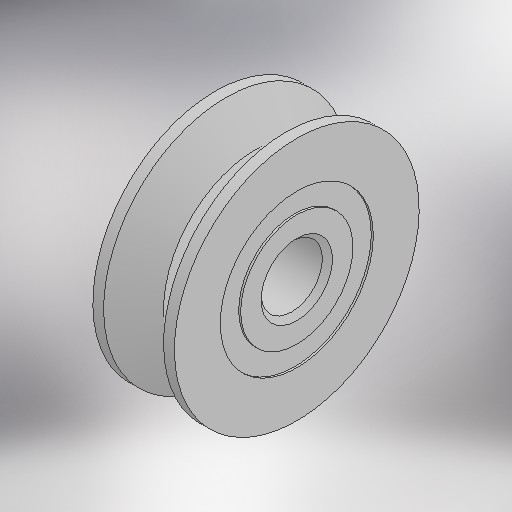
# Autodesk Inventor part: SZV4-12
Saved by Autodesk Inventor 2025.3 (Build 293356030, 356C)
## iProperties
Category: PARTsolutions
Company: MISUMI
Created: 2025-10-17
Part Number: SZV4-12
Material: Generic
Catalog Web Link: www.cadenas.de
Description: SZV, SZU, SZG-Stainless Steel Deep Groove Bearings
Vendor: MISUMI
Document SubType Name: Modeling
Designer: psAdmin
Manufacturer: MISUMI
Mass: 0.322411 g
Surface Area: 4.33482 cm^2
Volume: 0.322411 cm^3
Density: 1 g/cm^3
Appearance: PSOLRGB-175-175-175
PSOL_IDENT_0: {$CADENAS_DATA/23d-libs/misumi/metric/12_bearing_holders/szg.prj},166 {VTYP=3D},{NB=SZV4-12},{LINA=S
PSOL_IDENT_1: ZV4-12},{NN=SZV, SZU, SZG},{DATE=30.06.2021 12:59:26},{GEOMDATE=01.04.2010 04:21:00},{VERSION=},{LIN
PSOL_IDENT_2: EID=30},{WBVAR=TS,D},{WBNUMERIC=D}  {NB=SZV4-12},{LINA=SZV4-12},{KT=DUMMY},{PN=SZV4-12},{TS=V},{MATB=
PSOL_IDENT_3: 440C Stainless Steel},{DD=4},{D=12},{DALG=12,14},{B=4},{VD=9.06},{UD=0.00},{GD=0.00},{UR=0.00},{GR=0
PSOL_IDENT_4: },{C=0.25},{R=0.00},{CRR=542},{COO=186},{DSS=5.5},{DDHH=7.5},{WEIGHT=1.2},{TYPE=SZV}
NB: SZV4-12
NN: SZV, SZU, SZG
NT: Stainless Steel Deep Groove Bearings
NBSYN: $PN.
LINA: SZV4-12
CATALOG: Misumi
PN: SZV4-12
TS: SZV
MATB: 440C Stainless Steel
DD: 4
D: 12
B: 4
VD: 9.06
UD: 0
GD: 0
UR: 0
GR: 0
C: 0.25
R: 0
CRR: 542
COO: 186
DSS: 5.5
DDHH: 7.5
WEIGHT: 1.2
SUPPLIER: MISUMI
ARTICLENO: SZV4-12
BOMINFO: SZV4-12
CREATOR: CADENAS GmbH
Title: SZV4-12
Author: Cadenas PARTsolutions
Comments: Stainless Steel Deep Groove Bearings
Autodesk Inventor part; units mm, degrees
sketch "Sketch_1" plane through (0, 0, 0) normal (0, 0, 1) x (1, 0, 0)
  line L0 (2, 0) -> (0, 0)
  line L1 (-2, 6) -> (-2, 3.75)
  line L2 (-2, 3.75) -> (-1.9, 3.75)
  line L3 (-1.9, 3.75) -> (-1.9, 2.75)
  line L4 (-1.9, 2.75) -> (-2, 2.75)
  line L5 (-2, 2.75) -> (-2, 2.25)
  line L6 (-2, 2.25) -> (-1.75, 2)
  line L7 (-1.75, 2) -> (1.75, 2)
  line L8 (1.75, 2) -> (2, 2.25)
  line L9 (2, 2.25) -> (2, 2.75)
  line L10 (2, 2.75) -> (1.9, 2.75)
  line L11 (1.9, 2.75) -> (1.9, 3.75)
  line L12 (1.9, 3.75) -> (2, 3.75)
  line L13 (2, 3.75) -> (2, 6)
  line L14 (2, 6) -> (1.47, 6)
  line L15 (1.47, 6) -> (0, 4.53)
  line L16 (0, 4.53) -> (-1.47, 6)
  line L17 (-1.47, 6) -> (-2, 6)
  constraints: 36 end point
revolve "Revolution1" add sketch "Sketch_1" angle 360 about axis through (2, 0, 0) along (1, 0, 0)
ref_plane "to_bearing_XY" through (0, 0, 0) normal (1, 0, 0) x (0, 0, -1)
ref_plane "to_bearing_YZ" through (0, 0, 0) normal (0, 0, -1) x (0, 1, 0)
ref_plane "to_bearing_ZX" through (0, 0, 0) normal (0, 1, 0) x (1, 0, 0)
sketch "スケッチ2" plane through (0, 0, 0) normal (0, 0, 1) x (1, 0, 0)
  line L0 (-1.75, -2) -> (-1.75, 2) construction
  line L1 (-2, -2.25) -> (-2, 2.25) construction
  line L2 (1.75, -2) -> (1.75, 2) construction
  line L3 (-1.75, -2) -> (-1.75, 2) construction
  line L4 (2, -2.25) -> (2, 2.25) construction
  line L5 (1.75, -2) -> (1.75, 2) construction
  line L6 (2.0202, 2.25) -> (2.0202, 1.75) construction
  line L7 (1.75, 1.5) -> (-1.75, 1.5)
  line L8 (1.75, 1.5) -> (5.25, 1.5) construction
  line L9 (1.75, 1.5) -> (2, 1.75)
  line L10 (2, -2.25) -> (2, 2.25) projected
  line L11 (1.75, -2) -> (1.75, 2) projected
  line L12 (2, 2.25) -> (1.75, 2)
  line L13 (1.75, 2) -> (-1.75, 2)
  line L14 (-1.75, -2) -> (-1.75, 2) projected
  line L15 (-1.75, 2) -> (-2, 2.25)
  line L16 (-2, -2.25) -> (-2, 2.25) projected
  line L17 (-2, 2.25) -> (-2, 1.75)
  line L18 (-2, 2.25) -> (-1.5, 2.25) construction
  line L19 (-2, 1.75) -> (-1.75, 1.5)
  line L20 (-3.45, 0) -> (6.7, 0) projected
  point P0 (0, 0)
  dimension "d1" = 0.5
  dimension "d2" = 180
  dimension "d3" = 0.5
  dimension "d4" = 90
  constraints: 20 end point, 3 point on line, 2 equal length, 2 horizontal, 2 parallel, 2 perpendicular, 1 collinear
  measures "d1" distance of L6.start L6.end
  measures "d2" angle of L7 L8
  measures "d3" distance of L1.end L17.end
  measures "d4" angle of L17 L18
revolve "回転2" add sketch "スケッチ2" angle 360 about axis through (-10, 0, 0) along (1, 0, 0) contours L11 L12 L10 L9 | L7 L14 L13 L11 | L19 L16 L15 L14
body "Solid1"
